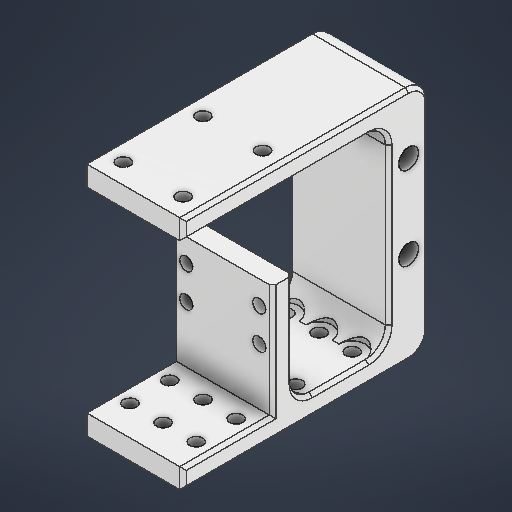
# Autodesk Inventor part: head stator
Saved by Autodesk Inventor 2026.2 (Build 302298010, 298A)
## iProperties
Created: 2026-04-27
Part Number: head stator
Material: ABS 플라스틱
Document SubType Name: Modeling
Designer: work
Density: 1.06 g/cm^3
Appearance: 매끄러움 - 흰색
Author: work
Autodesk Inventor part; units mm, degrees
ref_plane "YZ Plane" through (0, 0, 0) normal (1, 0, 0) x (0, 1, 0)
ref_plane "XZ Plane" through (0, 0, 0) normal (0, 1, 0) x (-1, 0, 0)
ref_plane "XY Plane" through (0, 0, 0) normal (0, 0, 1) x (1, 0, 0)
sketch "스케치1" plane through (0, 0, 0) normal (1, 0, 0) x (0, 1, 0)
  line L0 (-12.5, 25) -> (12.5, 25) construction
  line L1 (12.5, 25) -> (12.5, -25) construction
  line L2 (12.5, -25) -> (-12.5, -25) construction
  line L3 (-12.5, -25) -> (-12.5, 25) construction
  line L4 (-12.5, 25) -> (12.5, -25) construction
  line L5 (12.5, 25) -> (-12.5, -25) construction
  circle A0 centre (12.5, 25) radius 4 construction
  line L6 (-24.5, 34) -> (-0.5, 34) construction
  line L7 (-0.5, 34) -> (-0.5, 16) construction
  line L8 (-0.5, 16) -> (-24.5, 16) construction
  line L9 (-24.5, 16) -> (-24.5, 34) construction
  line L10 (-24.5, 34) -> (-0.5, 16) construction
  line L11 (-0.5, 34) -> (-24.5, 16) construction
  circle A1 centre (12.5, -25) radius 3
  circle A2 centre (-12.5, -25) radius 3
  line L12 (-18.5, -31) -> (18.5, -31)
  line L13 (18.5, -31) -> (18.5, -19) construction
  line L14 (18.5, -19) -> (-18.5, -19)
  line L15 (-18.5, -19) -> (-18.5, -31)
  line L16 (-18.5, -31) -> (18.5, -19) construction
  line L17 (18.5, -31) -> (-18.5, -19) construction
  line L18 (12.5, 25) -> (24.5, 25) construction
  line L19 (24.5, 43) -> (30.5, 43)
  line L20 (30.5, 43) -> (30.5, -31)
  line L21 (30.5, -31) -> (24.5, -31)
  line L22 (24.5, -31) -> (24.5, 43)
  line L23 (18.5, -19) -> (24.5, -19)
  line L24 (18.5, -31) -> (24.5, -31)
  line L25 (-18.5, 10) -> (-24.5, 10) construction
  line L26 (-24.5, 10) -> (-24.5, -31)
  line L27 (-24.5, -31) -> (-18.5, -31)
  line L28 (-18.5, -31) -> (-18.5, 10)
  line L29 (30.5, 37) -> (24.5, 37) construction
  line L30 (24.5, 37) -> (24.5, 13)
  line L31 (24.5, 13) -> (30.5, 13) construction
  line L32 (30.5, 13) -> (30.5, 37)
  line L33 (-6.5, 16) -> (-18.5, 16)
  line L34 (-18.5, 16) -> (-18.5, 10) construction
  line L35 (-18.5, 10) -> (-6.5, 10)
  line L36 (-6.5, 10) -> (-6.5, 16) construction
  line L37 (-0.5, 16) -> (-24.5, 16)
  line L38 (-24.5, 16) -> (-24.5, 10)
  line L39 (-24.5, 10) -> (-0.5, 10)
  line L40 (-0.5, 10) -> (-0.5, 16)
  line L41 (-18.5, -19) -> (-34.5, -19)
  line L42 (-34.5, -19) -> (-34.5, -31)
  line L43 (-34.5, -31) -> (-18.5, -31)
  line L44 (-18.5, -31) -> (-18.5, -19)
  line L45 (-34.5, -31) -> (-40.5, -31)
  line L46 (-40.5, -31) -> (-40.5, 16)
  line L47 (-40.5, 16) -> (-34.5, 16)
  line L48 (-34.5, 16) -> (-34.5, -31)
  line L49 (-34.5, 10) -> (-24.5, 10)
  line L50 (-24.5, 10) -> (-24.5, 16)
  line L51 (-24.5, 16) -> (-34.5, 16)
  line L52 (-34.5, 16) -> (-34.5, 10)
  point P0 (0, 0)
  point P1 (0, -25)
  point P2 (30.5, 25)
  point P3 (27.5, 13)
  point P4 (27.5, -31)
  point P5 (-12.5, 16)
  point P6 (-12.5, 10)
  point P7 (-18.5, 13)
  point P8 (-18.5, -19)
  point P9 (-6.5, 10)
  point P10 (-24.5, -31)
  dimension "d0" = 25
  dimension "d1" = 50
  dimension "d2" = 8
  dimension "d3" = 24
  dimension "d4" = 18
  dimension "d5" = 6
  dimension "d6" = 6
  dimension "d7" = 6
  dimension "d8" = 6
  dimension "d9" = 12
  dimension "d11" = 24
  dimension "d13" = 6
  dimension "d14" = 6
  dimension "d15" = 6
  dimension "d17" = 6
  dimension "d18" = 12
  dimension "d19" = 6
  dimension "d41" = 6
  dimension "d42" = 10
  constraints: 106 end point, 23 parallel, 17 midpoint, 13 horizontal, 11 perpendicular, 5 point on line, 3 centre point, 3 coincident
  measures "d0" distance of L1.end L2.end
  measures "d1" distance of L0.end L1.end
  measures "d2" diameter of A0
  measures "d3" distance of L7.end L8.end
  measures "d4" distance of L6.end L7.end
  measures "d5" diameter of A1
  measures "d6" diameter of A2
  measures "d7" distance from line of L1.end L13
  measures "d8" distance from line of L14 L1.end
  measures "d9" distance of L18.end L18.start
  measures "d11" distance from line of point (27.5, 13) L29
  measures "d13" distance between parallel lines of L22 L20
  measures "d14" distance between parallel lines of L29 L19
  measures "d15" distance between parallel lines of L28 L26
  measures "d17" distance of L33.end L34.end
  measures "d18" distance from line of point (-18.5, 13) L36
  measures "d19" distance between parallel lines of L38 L34
  measures "d41" distance between parallel lines of L46 L48
  measures "d42" distance between parallel lines of L52 L38
extrude "돌출1" add sketch "스케치1" along normal blind 30 contours L15 L14 L23 L22 L24 L12 | L27 L26 L41 L15 | L43 L42 L41 L26 | L22 L19 L20 L21 | L39 L38 L37 L33 L40 L35 | L45 L46 L47 L48 L42 | L49 L48 L51 L38
sketch "스케치2" plane through (0, 30.5, 43) normal (0, 1, 0) x (1, 0, 0)
  line L0 (0, 74) -> (0, 0) projected
  line L1 (0, 0) -> (30, 0) projected
  line L2 (30, 74) -> (30, 0) projected
  line L3 (0, 74) -> (30, 74) projected
  line L4 (15, 0) -> (15, 74) construction
  line L5 (0, 37) -> (30, 37) construction
  line L6 (24, 30) -> (6, 30) construction
  line L7 (6, 30) -> (6, 6) construction
  line L8 (6, 6) -> (24, 6) construction
  line L9 (24, 6) -> (24, 30) construction
  line L10 (24, 30) -> (6, 6) construction
  line L11 (6, 30) -> (24, 6) construction
  circle A0 centre (6, 6) radius 2
  circle A1 centre (24, 6) radius 2
  circle A2 centre (24, 30) radius 2
  circle A3 centre (6, 30) radius 2
  point P0 (0, 43)
  point P1 (15, 18)
  dimension "d22" = 6
  dimension "d23" = 24
  dimension "d24" = 18
  dimension "d25" = 4
  dimension "d26" = 4
  dimension "d27" = 4
  dimension "d28" = 4
  constraints: 16 end point, 6 midpoint, 4 centre point, 4 coincident, 2 parallel, 1 horizontal, 1 perpendicular, 1 point on line
  measures "d22" distance between parallel lines of L1 L8
  measures "d23" distance of L6.end L7.end
  measures "d24" distance of L7.end L8.end
  measures "d25" diameter of A0
  measures "d26" diameter of A1
  measures "d27" diameter of A2
  measures "d28" diameter of A3
extrude "돌출2" cut sketch "스케치2" against normal up to surface (31 mm away) contours A0 | A1 | A2 | A3
fillet "모깎기1" radius 6 6 edges at (15, 30.5, -31) (15, 24.5, -19) (15, -40.5, -31) (15, -34.5, -19) (15, -34.5, 10) (15, -40.5, 16)
sketch "스케치4" plane through (0, -40.5, 16) normal (0, 0, 1) x (1, 0, 0)
  line L0 (30, 31) -> (30, 25) projected
  line L1 (0, 31) -> (0, 25) projected
  line L2 (0, 28) -> (30, 28) construction
  line L3 (26, 23) -> (4, 23) construction
  line L4 (4, 23) -> (4, 33) construction
  line L5 (4, 33) -> (26, 33) construction
  line L6 (26, 33) -> (26, 23) construction
  line L7 (26, 23) -> (4, 33) construction
  line L8 (4, 23) -> (26, 33) construction
  circle A0 centre (4, 23) radius 2
  circle A1 centre (4, 33) radius 2
  circle A2 centre (26, 33) radius 2
  circle A3 centre (26, 23) radius 2
  point P0 (0, 40.5)
  point P1 (15, 28)
  dimension "d44" = 10
  dimension "d45" = 4
  dimension "d46" = 4
  dimension "d47" = 4
  dimension "d48" = 4
  dimension "d49" = 4
  constraints: 14 end point, 5 midpoint, 4 centre point, 4 coincident, 2 parallel, 1 horizontal, 1 perpendicular
  measures "d44" distance of L3.end L4.end
  measures "d45" distance between parallel lines of L1 L4
  measures "d46" diameter of A0
  measures "d47" diameter of A1
  measures "d48" diameter of A2
  measures "d49" diameter of A3
extrude "돌출4" cut sketch "스케치4" against normal blind 30
sketch "스케치5" plane through (0, 0, 0) normal (-1, 0, 0) x (0, 0, 1)
  line L0 (16, -9.5) -> (10, -9.5) projected
  circle A0 centre (-25, 12.5) radius 3 projected
  circle A1 centre (-25, -12.5) radius 3 projected
  arc A2 (10, -40.5) -> (16, -34.5) centre (10, -34.5) ccw projected
  line L1 (16, -0.5) -> (16, -34.5) projected
  line L2 (10, -0.5) -> (16, -0.5) projected
  line L3 (10, -28.5) -> (10, -0.5) projected
  arc A3 (4, -34.5) -> (10, -28.5) centre (4, -28.5) ccw projected
  line L4 (-13, -34.5) -> (4, -34.5) projected
  arc A4 (-19, -28.5) -> (-13, -34.5) centre (-13, -28.5) ccw projected
  line L5 (-19, 18.5) -> (-19, -28.5) projected
  arc A5 (-13, 24.5) -> (-19, 18.5) centre (-13, 18.5) ccw projected
  line L6 (43, 24.5) -> (-13, 24.5) projected
  line L7 (43, 30.5) -> (43, 24.5) projected
  line L8 (-25, 30.5) -> (43, 30.5) projected
  arc A6 (-25, 30.5) -> (-31, 24.5) centre (-25, 24.5) ccw projected
  line L9 (-31, -34.5) -> (-31, 24.5) projected
  arc A7 (-31, -34.5) -> (-25, -40.5) centre (-25, -34.5) ccw projected
  line L10 (10, -40.5) -> (-25, -40.5) projected
  line L11 (4, -34.5) -> (43, -34.5)
  line L12 (43, -34.5) -> (43, -40.5)
  line L13 (43, -40.5) -> (4, -40.5)
  line L14 (4, -40.5) -> (4, -34.5)
  line L15 (43, 30.5) -> (43, 24.5) projected
  point P0 (0, 0)
  dimension "d52" = 6
  constraints: 8 end point, 2 parallel, 1 collinear, 1 horizontal, 1 perpendicular, 1 point on circle, 1 point on line
  measures "d52" distance of L13.end L11.start
extrude "돌출5" add sketch "스케치5" against normal up to surface (30 mm away) contours L11 L12 L13 A2
sketch "스케치6" plane through (0, -40.5, -25) normal (0, -1, 0) x (1, 0, 0)
  line L0 (0, 68) -> (0, 0) construction
  line L1 (30, 0) -> (0, 0) construction
  line L2 (30, 68) -> (30, 0) construction
  line L3 (0, 68) -> (30, 68) construction
  line L4 (25, 65) -> (5, 65) construction
  line L5 (5, 65) -> (5, 5) construction
  line L6 (5, 5) -> (25, 5) construction
  line L7 (25, 5) -> (25, 65) construction
  line L8 (0, 35) -> (30, 35) construction
  line L9 (25, 65) -> (5, 5) construction
  line L10 (5, 65) -> (25, 5) construction
  line L11 (6, 35) -> (2, 35) construction
  line L12 (6, 35) -> (2, 35) construction
  line L13 (0, 35) -> (0, 41) construction
  line L14 (0, 41) -> (30, 41) construction
  line L15 (30, 35) -> (30, 41) construction
  line L16 (0, 35) -> (30, 35) construction
  line L17 (25, 47) -> (5, 47) construction
  line L18 (5, 47) -> (5, 65) construction
  line L19 (5, 65) -> (25, 65) construction
  line L20 (25, 65) -> (25, 47) construction
  line L21 (30, 6) -> (0, 6) construction
  line L22 (25, 12) -> (5, 12) construction
  line L23 (5, 12) -> (5, 29) construction
  line L24 (5, 29) -> (25, 29) construction
  line L25 (25, 29) -> (25, 12) construction
  line L26 (25, 59) -> (5, 59) construction
  line L27 (15, 5) -> (15, 65) construction
  point P0 (0, 25)
  point P1 (15, 35)
  point P2 (15, 47)
  point P3 (15, 59)
  point P4 (15, 29)
  point P5 (15, 12)
  dimension "d56" = 5
  dimension "d57" = 5
  dimension "d58" = 6
  dimension "d59" = 6
  dimension "d60" = 6
  dimension "d61" = 6
  constraints: 32 end point, 9 midpoint, 9 point on line, 8 coincident, 6 parallel, 4 perpendicular, 3 horizontal
  measures "d56" distance between parallel lines of L0 L5
  measures "d57" distance between parallel lines of L1 L6
  measures "d58" distance between parallel lines of L8 L24
  measures "d59" distance between parallel lines of L21 L22
  measures "d60" distance between parallel lines of L14 L17
  measures "d61" distance between parallel lines of L4 L26
hole "구멍1" at (25, -40.5, -13) at (25, -40.5, 4) at (25, -40.5, 34) at (25, -40.5, 22) at (5, -40.5, 34) at (5, -40.5, 22) at (5, -40.5, 4) at (5, -40.5, -13) at (15, -40.5, 22) at (15, -40.5, 34) at (15, -40.5, 4) at (15, -40.5, -13) direction (0, 1, 0) diameter 4 depth 6 tip angle 118
chamfer "모따기1" distance 1 angle 45 10 edges at (0, -40.5, 9) (0, -38.7426, -29.2426) (0, -5, -31) (0, 28.7426, -29.2426) (0, 30.5, 9) (30, -40.5, 9) (30, -38.7426, -29.2426) (30, -5, -31) (30, 28.7426, -29.2426) (30, 30.5, 9)
sketch "스케치7" plane through (0, -34.5, 4) normal (0, 1, 0) x (1, 0, 0)
  line L0 (29, -39) -> (29, 29) projected
  line L1 (1, -39) -> (29, -39) projected
  line L2 (1, 29) -> (1, -39) projected
  line L3 (29, 29) -> (1, 29) projected
  circle A0 centre (15, 17) radius 2 projected
  circle A1 centre (15, 0) radius 2 projected
  circle A2 centre (15, -30) radius 2 projected
  circle A3 centre (15, -18) radius 2 projected
  circle A4 centre (5, 17) radius 2 projected
  circle A5 centre (5, 0) radius 2 projected
  circle A6 centre (5, -18) radius 2 projected
  circle A7 centre (5, -30) radius 2 projected
  circle A8 centre (25, -18) radius 2 projected
  circle A9 centre (25, -30) radius 2 projected
  circle A10 centre (25, 0) radius 2 projected
  circle A11 centre (25, 17) radius 2 projected
  circle A12 centre (25, 17) radius 4
  circle A13 centre (25, 0) radius 4
  circle A14 centre (15, 0) radius 4
  circle A15 centre (15, 17) radius 4
  circle A16 centre (5, 17) radius 4
  circle A17 centre (5, 0) radius 4
  point P0 (0, 4)
  dimension "d72" = 8
  dimension "d73" = 8
  dimension "d74" = 8
  dimension "d75" = 8
  dimension "d76" = 8
  dimension "d77" = 8
  constraints: 6 centre point, 1 coincident
  measures "d72" diameter of A12
  measures "d73" diameter of A13
  measures "d74" diameter of A14
  measures "d75" diameter of A15
  measures "d76" diameter of A16
  measures "d77" diameter of A17
extrude "돌출6" cut sketch "스케치7" along normal blind 10 contours A13 | A12 | A16 | A17 | A0 | A1 | A4 | A5 | A10 | A11 | A14 | A15
chamfer "모따기2" distance 1 angle 45 22 edges at (0, 22.7426, -17.2426) (0, -5, -19) (0, -32.7426, -17.2426) (0, -34.5, -4.5) (0, -32.7426, 8.2426) (0, -14.5, 10) (0, 24.5, 15) (0, 27, 43) (30, -37, 43) (30, -34.5, 29.5) (30, -17.5, 16) (30, -32.7426, 8.2426) (30, -34.5, -4.5) (30, -32.7426, -17.2426) (30, -5, -19) (30, 22.7426, -17.2426) (30, 24.5, 15) (30, -14.5, 10) (0, -17.5, 16) (0, -34.5, 29.5) (0, -37, 43) (30, 27, 43)
equation "\"d67\" = d59"
